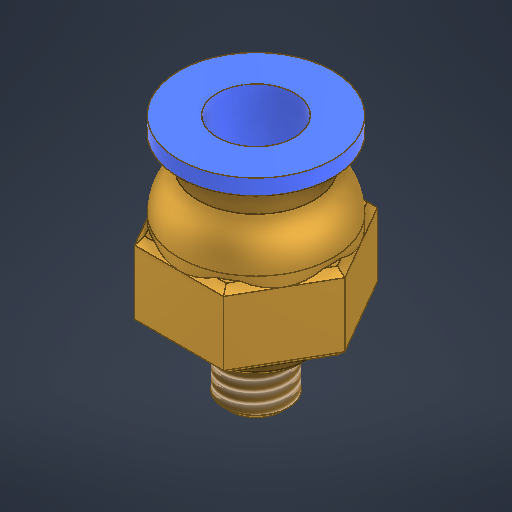
# Autodesk Inventor part: PC6-M5
Saved by Autodesk Inventor 2026.2 (Build 302298010, 298A)
## iProperties
Created: 2026-05-07
Part Number: PC6-M5
Material: 황동, 연질 노란색
Document SubType Name: Modeling
Designer: work
Density: 8.47 g/cm^3
Appearance: 황동 - 새틴
Author: work
Autodesk Inventor part; units mm, degrees
ref_plane "YZ Plane" through (0, 0, 0) normal (1, 0, 0) x (0, 1, 0)
ref_plane "XZ Plane" through (0, 0, 0) normal (0, 1, 0) x (-1, 0, 0)
ref_plane "XY Plane" through (0, 0, 0) normal (0, 0, 1) x (1, 0, 0)
sketch "스케치1" plane through (0, 0, 0) normal (0, 1, 0) x (-1, 0, 0)
  line L0 (6.928203, 0) -> (3.464102, -6)
  line L1 (3.464102, -6) -> (-3.464102, -6)
  line L2 (-3.464102, -6) -> (-6.928203, 0)
  line L3 (-6.928203, 0) -> (-3.464102, 6)
  line L4 (-3.464102, 6) -> (3.464102, 6)
  line L5 (3.464102, 6) -> (6.928203, 0)
  line L6 (6.928203, 0) -> (0, 0) construction
  line L7 (0, 0) -> (5.196152, -3) construction
  line L8 (0, 0) -> (-5.196152, 3) construction
  dimension "d0" = 12
  constraints: 18 end point, 2 midpoint, 1 coincident, 1 horizontal, 13 other
  measures "d0" distance between parallel lines of L3 L0
extrude "돌출1" add sketch "스케치1" along normal blind 6
sketch "스케치2" plane through (0, 0, 0) normal (0, -1, 0) x (1, 0, 0)
  circle A0 centre (0, 0) radius 4
  dimension "d3" = 8
  constraints: 1 centre point, 1 coincident
  measures "d3" diameter of A0
extrude "돌출2" add sketch "스케치2" along normal blind 2
sketch "스케치3" plane through (0, -2, 0) normal (0, -1, 0) x (1, 0, 0)
  circle A0 centre (0, 0) radius 2.5
  dimension "d6" = 5
  constraints: 1 centre point, 1 coincident
  measures "d6" diameter of A0
extrude "돌출3" add sketch "스케치3" along normal blind 4
thread "스레드1" size "M5x0.8" class "6g" standard "ISO Metric profile" full length
sketch "스케치4" plane through (0, 0, 0) normal (0, 0, 1) x (1, 0, 0)
  line L0 (3.464102, 6) -> (-3.464102, 6)
  line L1 (0, 6) -> (0, 16.932994)
  line L2 (0, 6) -> (6, 6)
  line L3 (6.928203, 6) -> (3.464102, 6)
  line L4 (0, 11) -> (4.5, 11)
  line L5 (4.5, 11) -> (4.5, 9.5)
  arc A0 (6, 6.377501) -> (4.5, 9.5) centre (2, 6.377501) ccw
  line L6 (6, 6.377501) -> (6, 6)
  line L7 (3, 11) -> (3, 13)
  line L8 (3, 13) -> (6, 13)
  line L9 (6, 13) -> (6, 11.8)
  line L10 (6, 11.8) -> (4, 11.8)
  line L11 (4, 11.8) -> (4, 11)
  line L12 (6.928203, 0) -> (3.464102, 0)
  point P0 (0, 0)
  point P1 (4.5, 13)
  dimension "d11" = 6
  dimension "d12" = 4.5
  dimension "d13" = 1.5
  dimension "d14" = 4
  dimension "d15" = 3.5
  dimension "d16" = 1.2
  dimension "d17" = 6
  dimension "d19" = 8
  dimension "d21" = 7
  dimension "d22" = 12
  constraints: 20 end point, 5 perpendicular, 4 point on line, 3 vertical, 2 midpoint, 2 point on circle, 1 centre point, 1 horizontal, 1 tangent
  measures "d11" distance of L1.start L2.end
  measures "d12" distance of L4.start L4.end
  measures "d13" distance of L4.end L5.end
  measures "d14" radius of A0
  measures "d15" distance from line of L2 L5.end
  measures "d16" distance of L8.end L9.end
  measures "d17" diameter of L7 L1
  measures "d19" diameter of L11 L1
  measures "d21" distance between parallel lines of L3 L8
  measures "d22" diameter of L9 L1
revolve "회전1" add sketch "스케치4" angle 360 about axis through (0, 6, 0) along (0, 1, 0)
sketch "스케치5" plane through (0, 11, 0) normal (0, 1, 0) x (1, 0, 0)
  circle A0 centre (0, 0) radius 2.5 projected
  circle A1 centre (0, 0) radius 3
  dimension "d24" = 6
  constraints: 1 centre point, 1 coincident
  measures "d24" diameter of A1
extrude "돌출4" cut sketch "스케치5" against normal blind 10 contours A0 | A1
sketch "스케치6" plane through (0, -6, 0) normal (0, -1, 0) x (1, 0, 0)
  circle A0 centre (0, 0) radius 1
  dimension "d27" = 2
  constraints: 1 centre point, 1 coincident
  measures "d27" diameter of A0
extrude "돌출5" cut sketch "스케치6" against normal through all
chamfer "모따기1" distance 0.5 angle 45 2 edges at (-2.5, -6, 0) (-4, -2, 0)
chamfer "모따기2" distance 0.5 angle 45 18 edges at (-5.1962, 0, 3) (0, 0, 6) (5.1962, 0, 3) (5.1962, 0, -3) (0, 0, -6) (-5.1962, 0, -3) (-4.3301, 6, -4.5) (-6.0622, 6, -1.5) (-6.0622, 6, 1.5) (-4.3301, 6, 4.5) (-1.7321, 6, 6) (1.7321, 6, 6) (4.3301, 6, 4.5) (6.0622, 6, 1.5) (6.0622, 6, -1.5) (4.3301, 6, -4.5) (1.7321, 6, -6) (-1.7321, 6, -6)
